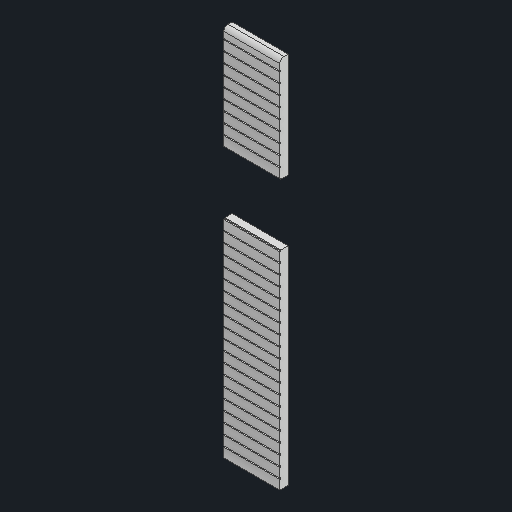
# Autodesk Inventor part: 7_1_2_vollet_cote_avant
Saved by Autodesk Inventor 2026 (Build 300175000, 175)
## iProperties
Created: 2025-06-21
Part Number: 7_1_2_vollet_cote_avant
Material: Generic
Document SubType Name: Modeling
Designer: remg9
Density: 1 g/cm^3
Appearance: Default
Author: remg9
Autodesk Inventor part; units mm, degrees
ref_plane "YZ Plane" through (0, 0, 0) normal (1, 0, 0) x (0, 1, 0)
ref_plane "XZ Plane" through (0, 0, 0) normal (0, 1, 0) x (-1, 0, 0)
ref_plane "XY Plane" through (0, 0, 0) normal (0, 0, 1) x (1, 0, 0)
sketch "Sketch1" plane through (0, 0, 0) normal (0, 0, 1) x (1, 0, 0)
  line L0 (0, 0) -> (27, 0)
  line L1 (27, 0) -> (27, 180)
  line L2 (27, 180) -> (0, 180)
  line L3 (0, 180) -> (0, 0)
  dimension "d0" = 180
  dimension "d1" = 27
  constraints: 8 end point, 2 parallel, 1 horizontal, 1 perpendicular
  measures "d0" distance of L0.end L1.end
  measures "d1" distance of L1.end L2.end
extrude "Extrusion1" add sketch "Sketch1" along normal blind 4
sketch "Sketch2" plane through (0, 0, 4) normal (0, 0, 1) x (1, 0, 0)
  line L0 (0, 175) -> (27, 175)
  line L1 (27, 175) -> (27, 174.5)
  line L2 (27, 174.5) -> (0, 174.5)
  line L3 (0, 174.5) -> (0, 175)
  line L4 (27, 0) -> (27, 180) projected
  line L5 (0, 180) -> (0, 0) projected
  line L6 (0, 170) -> (27, 170)
  line L7 (27, 170) -> (27, 169.5)
  line L8 (27, 169.5) -> (0, 169.5)
  line L9 (0, 169.5) -> (0, 170)
  line L10 (0, 165) -> (27, 165)
  line L11 (27, 165) -> (27, 164.5)
  line L12 (27, 164.5) -> (0, 164.5)
  line L13 (0, 164.5) -> (0, 165)
  line L14 (0, 160) -> (27, 160)
  line L15 (27, 160) -> (27, 159.5)
  line L16 (27, 159.5) -> (0, 159.5)
  line L17 (0, 159.5) -> (0, 160)
  line L18 (0, 155) -> (27, 155)
  line L19 (27, 155) -> (27, 154.5)
  line L20 (27, 154.5) -> (0, 154.5)
  line L21 (0, 154.5) -> (0, 155)
  line L22 (0, 150) -> (27, 150)
  line L23 (27, 150) -> (27, 149.5)
  line L24 (27, 149.5) -> (0, 149.5)
  line L25 (0, 149.5) -> (0, 150)
  line L26 (0, 145) -> (27, 145)
  line L27 (27, 145) -> (27, 144.5)
  line L28 (27, 144.5) -> (0, 144.5)
  line L29 (0, 144.5) -> (0, 145)
  line L30 (0, 140) -> (27, 140)
  line L31 (27, 140) -> (27, 139.5)
  line L32 (27, 139.5) -> (0, 139.5)
  line L33 (0, 139.5) -> (0, 140)
  line L34 (0, 135) -> (27, 135)
  line L35 (27, 135) -> (27, 134.5)
  line L36 (27, 134.5) -> (0, 134.5)
  line L37 (0, 134.5) -> (0, 135)
  line L38 (0, 130) -> (27, 130)
  line L39 (27, 130) -> (27, 129.5)
  line L40 (27, 129.5) -> (0, 129.5)
  line L41 (0, 129.5) -> (0, 130)
  line L42 (0, 125) -> (27, 125)
  line L43 (27, 125) -> (27, 124.5)
  line L44 (27, 124.5) -> (0, 124.5)
  line L45 (0, 124.5) -> (0, 125)
  line L46 (0, 120) -> (27, 120)
  line L47 (27, 120) -> (27, 119.5)
  line L48 (27, 119.5) -> (0, 119.5)
  line L49 (0, 119.5) -> (0, 120)
  line L50 (0, 115) -> (27, 115)
  line L51 (27, 115) -> (27, 114.5)
  line L52 (27, 114.5) -> (0, 114.5)
  line L53 (0, 114.5) -> (0, 115)
  line L54 (0, 110) -> (27, 110)
  line L55 (27, 110) -> (27, 109.5)
  line L56 (27, 109.5) -> (0, 109.5)
  line L57 (0, 109.5) -> (0, 110)
  line L58 (0, 105) -> (27, 105)
  line L59 (27, 105) -> (27, 104.5)
  line L60 (27, 104.5) -> (0, 104.5)
  line L61 (0, 104.5) -> (0, 105)
  line L62 (0, 100) -> (27, 100)
  line L63 (27, 100) -> (27, 99.5)
  line L64 (27, 99.5) -> (0, 99.5)
  line L65 (0, 99.5) -> (0, 100)
  line L66 (0, 95) -> (27, 95)
  line L67 (27, 95) -> (27, 94.5)
  line L68 (27, 94.5) -> (0, 94.5)
  line L69 (0, 94.5) -> (0, 95)
  line L70 (0, 90) -> (27, 90)
  line L71 (27, 90) -> (27, 89.5)
  line L72 (27, 89.5) -> (0, 89.5)
  line L73 (0, 89.5) -> (0, 90)
  line L74 (0, 85) -> (27, 85)
  line L75 (27, 85) -> (27, 84.5)
  line L76 (27, 84.5) -> (0, 84.5)
  line L77 (0, 84.5) -> (0, 85)
  line L78 (0, 80) -> (27, 80)
  line L79 (27, 80) -> (27, 79.5)
  line L80 (27, 79.5) -> (0, 79.5)
  line L81 (0, 79.5) -> (0, 80)
  line L82 (0, 75) -> (27, 75)
  line L83 (27, 75) -> (27, 74.5)
  line L84 (27, 74.5) -> (0, 74.5)
  line L85 (0, 74.5) -> (0, 75)
  line L86 (0, 70) -> (27, 70)
  line L87 (27, 70) -> (27, 69.5)
  line L88 (27, 69.5) -> (0, 69.5)
  line L89 (0, 69.5) -> (0, 70)
  line L90 (0, 65) -> (27, 65)
  line L91 (27, 65) -> (27, 64.5)
  line L92 (27, 64.5) -> (0, 64.5)
  line L93 (0, 64.5) -> (0, 65)
  line L94 (0, 60) -> (27, 60)
  line L95 (27, 60) -> (27, 59.5)
  line L96 (27, 59.5) -> (0, 59.5)
  line L97 (0, 59.5) -> (0, 60)
  line L98 (0, 55) -> (27, 55)
  line L99 (27, 55) -> (27, 54.5)
  line L100 (27, 54.5) -> (0, 54.5)
  line L101 (0, 54.5) -> (0, 55)
  line L102 (0, 50) -> (27, 50)
  line L103 (27, 50) -> (27, 49.5)
  line L104 (27, 49.5) -> (0, 49.5)
  line L105 (0, 49.5) -> (0, 50)
  line L106 (0, 45) -> (27, 45)
  line L107 (27, 45) -> (27, 44.5)
  line L108 (27, 44.5) -> (0, 44.5)
  line L109 (0, 44.5) -> (0, 45)
  line L110 (0, 40) -> (27, 40)
  line L111 (27, 40) -> (27, 39.5)
  line L112 (27, 39.5) -> (0, 39.5)
  line L113 (0, 39.5) -> (0, 40)
  line L114 (0, 35) -> (27, 35)
  line L115 (27, 35) -> (27, 34.5)
  line L116 (27, 34.5) -> (0, 34.5)
  line L117 (0, 34.5) -> (0, 35)
  line L118 (0, 30) -> (27, 30)
  line L119 (27, 30) -> (27, 29.5)
  line L120 (27, 29.5) -> (0, 29.5)
  line L121 (0, 29.5) -> (0, 30)
  line L122 (0, 25) -> (27, 25)
  line L123 (27, 25) -> (27, 24.5)
  line L124 (27, 24.5) -> (0, 24.5)
  line L125 (0, 24.5) -> (0, 25)
  line L126 (0, 20) -> (27, 20)
  line L127 (27, 20) -> (27, 19.5)
  line L128 (27, 19.5) -> (0, 19.5)
  line L129 (0, 19.5) -> (0, 20)
  line L130 (0, 15) -> (27, 15)
  line L131 (27, 15) -> (27, 14.5)
  line L132 (27, 14.5) -> (0, 14.5)
  line L133 (0, 14.5) -> (0, 15)
  line L134 (0, 10) -> (27, 10)
  line L135 (27, 10) -> (27, 9.5)
  line L136 (27, 9.5) -> (0, 9.5)
  line L137 (0, 9.5) -> (0, 10)
  line L138 (0, 5) -> (27, 5)
  line L139 (27, 5) -> (27, 4.5)
  line L140 (27, 4.5) -> (0, 4.5)
  line L141 (0, 4.5) -> (0, 5)
  line L142 (27, 180) -> (0, 180) projected
  point P0 (0, 4.5)
  point P1 (27, 4.5)
  point P2 (27, 5)
  point P3 (0, 9.5)
  point P4 (27, 9.5)
  point P5 (27, 10)
  point P6 (0, 14.5)
  point P7 (27, 14.5)
  point P8 (27, 15)
  point P9 (0, 19.5)
  point P10 (27, 19.5)
  point P11 (27, 20)
  point P12 (0, 24.5)
  point P13 (27, 24.5)
  point P14 (27, 25)
  point P15 (0, 29.5)
  point P16 (27, 29.5)
  point P17 (27, 30)
  point P18 (0, 34.5)
  point P19 (27, 34.5)
  point P20 (27, 35)
  point P21 (0, 39.5)
  point P22 (27, 39.5)
  point P23 (27, 40)
  point P24 (0, 44.5)
  point P25 (27, 44.5)
  point P26 (27, 45)
  point P27 (0, 49.5)
  point P28 (27, 49.5)
  point P29 (27, 50)
  point P30 (0, 54.5)
  point P31 (27, 54.5)
  point P32 (27, 55)
  point P33 (0, 59.5)
  point P34 (27, 59.5)
  point P35 (27, 60)
  point P36 (0, 64.5)
  point P37 (27, 64.5)
  point P38 (27, 65)
  point P39 (0, 69.5)
  point P40 (27, 69.5)
  point P41 (27, 70)
  point P42 (0, 74.5)
  point P43 (27, 74.5)
  point P44 (27, 75)
  point P45 (0, 79.5)
  point P46 (27, 79.5)
  point P47 (27, 80)
  point P48 (0, 84.5)
  point P49 (27, 84.5)
  point P50 (27, 85)
  point P51 (0, 89.5)
  point P52 (27, 89.5)
  point P53 (27, 90)
  point P54 (0, 94.5)
  point P55 (27, 94.5)
  point P56 (27, 95)
  point P57 (0, 99.5)
  point P58 (27, 99.5)
  point P59 (27, 100)
  point P60 (0, 104.5)
  point P61 (27, 104.5)
  point P62 (27, 105)
  point P63 (0, 109.5)
  point P64 (27, 109.5)
  point P65 (27, 110)
  point P66 (0, 114.5)
  point P67 (27, 114.5)
  point P68 (27, 115)
  point P69 (0, 119.5)
  point P70 (27, 119.5)
  point P71 (27, 120)
  point P72 (0, 124.5)
  point P73 (27, 124.5)
  point P74 (27, 125)
  point P75 (0, 129.5)
  point P76 (27, 129.5)
  point P77 (27, 130)
  point P78 (0, 134.5)
  point P79 (27, 134.5)
  point P80 (27, 135)
  point P81 (0, 139.5)
  point P82 (27, 139.5)
  point P83 (27, 140)
  point P84 (0, 144.5)
  point P85 (27, 144.5)
  point P86 (27, 145)
  point P87 (0, 149.5)
  point P88 (27, 149.5)
  point P89 (27, 150)
  point P90 (0, 154.5)
  point P91 (27, 154.5)
  point P92 (27, 155)
  point P93 (0, 159.5)
  point P94 (27, 159.5)
  point P95 (27, 160)
  point P96 (0, 164.5)
  point P97 (27, 164.5)
  point P98 (27, 165)
  point P99 (0, 169.5)
  point P100 (27, 169.5)
  point P101 (27, 170)
  dimension "d4" = 0.5
  dimension "d7" = 5
  dimension "d12" = 5
  constraints: 280 end point, 136 vertical alignment, 70 parallel, 68 collinear, 2 vertical, 1 horizontal, 1 perpendicular
  measures "d4" distance between parallel lines of L2 L0
  measures "d7" distance of L0.start L6.start
  measures "d12" distance between parallel lines of L142 L0
extrude "Extrusion2" cut sketch "Sketch2" against normal blind 0.5 contours L0 L1 L2 L3 | L6 L4 L8 L5 | L10 L4 L12 L5 | L14 L4 L16 L5 | L18 L4 L20 L5 | L22 L4 L24 L5 | L26 L4 L28 L5 | L30 L4 L32 L5 | L34 L4 L36 L5 | L38 L4 L40 L5 | L42 L4 L44 L5 | L46 L4 L48 L5 | L50 L4 L52 L5 | L54 L4 L56 L5 | L58 L4 L60 L5 | L62 L4 L64 L5 | L66 L4 L68 L5 | L70 L4 L72 L5 | L74 L4 L76 L5 | L78 L4 L80 L5 | L82 L4 L84 L5 | L86 L4 L88 L5 | L90 L4 L92 L5 | L94 L4 L96 L5 | L98 L4 L100 L5 | L102 L4 L104 L5 | L106 L4 L108 L5 | L110 L4 L112 L5 | L114 L4 L116 L5 | L118 L4 L120 L5 | L122 L4 L124 L5 | L126 L4 L128 L5 | L130 L4 L132 L5 | L134 L4 L136 L5 | L138 L4 L140 L5
fillet "Fillet1" radius 2 1 edges at (13.5, 180, 4)
sketch "Sketch3" plane through (0, 0, 4) normal (0, 0, 1) x (1, 0, 0)
  line L0 (0, 129.5) -> (27, 129.5)
  line L1 (27, 129.5) -> (27, 100)
  line L2 (27, 100) -> (0, 100)
  line L3 (0, 100) -> (0, 129.5)
  line L4 (27, 129.5) -> (0, 129.5) projected
  line L5 (0, 129.5) -> (0, 125) projected
  line L6 (27, 125) -> (27, 129.5) projected
  line L7 (0, 100) -> (27, 100) projected
  point P0 (0, 0)
  constraints: 8 end point, 4 collinear, 2 parallel, 1 horizontal, 1 perpendicular
extrude "Extrusion3" cut sketch "Sketch3" against normal blind 10
body "Solid1"
